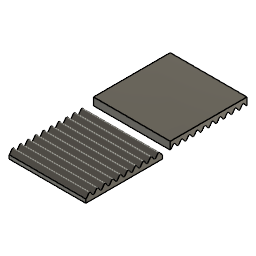
Mould texture v1 (Autodesk Fusion 360 design; units mm, degrees)
part number: 2026-06-02-12-18-22-877
Autodesk Fusion 360 part; units mm, degrees
sketch "Sketch1" plane through (0, 0, 0) normal (1, 0, 0) x (0, 1, 0)
  line L0 (0, 0) -> (100, 0)
  spline S0 degree 5 poles (0, 5) (0.1905, 5) (0.5782, 5.1) (1.1803, 5.55) (2.0142, 6.654) (3.0561, 8.346) (4.0573, 9.726) (4.9964, 10.266) (5.9504, 9.726) (6.9802, 8.346) (8.0326, 6.654) (9.0551, 5.274) (9.9993, 4.734) (10.9464, 5.274) (11.9742, 6.654) (13.0285, 8.346) (14.0548, 9.726) (14.9998, 10.266) (15.9457, 9.726) (16.9738, 8.346) (18.0288, 6.654) (19.0554, 5.274) (19.9994, 4.734) (20.9459, 5.274) (21.9778, 6.654) (23.0362, 8.346) (24.0625, 9.726) (25, 10.266) (25.9375, 9.726) (26.9638, 8.346) (28.0222, 6.654) (29.0541, 5.274) (30.0006, 4.734) (30.9447, 5.274) (31.9714, 6.654) (33.0264, 8.346) (34.0544, 9.726) (35.0001, 10.266) (35.9453, 9.726) (36.9723, 8.346) (38.027, 6.654) (39.0544, 5.274) (40.0001, 4.734) (40.9454, 5.274) (41.9718, 6.654) (43.0261, 8.3459) (44.0537, 9.7259) (45.0006, 10.266) (45.945, 9.726) (46.9676, 8.3457) (48.0187, 6.6535) (49.0469, 5.2736) (50.0003, 4.734) (50.9524, 5.2744) (51.9779, 6.6545) (53.028, 8.3462) (54.0524, 9.726) (55.0013, 10.266) (55.9449, 9.726) (56.9582, 8.346) (58.0016, 6.6539) (59.0314, 5.2739) (60.0013, 4.734) (60.9659, 5.2741) (61.9848, 6.6542) (63.0217, 8.3461) (64.0396, 9.726) (65.0008, 10.266) (65.9588, 9.726) (66.9699, 8.346) (68.0023, 6.654) (69.0234, 5.274) (69.9988, 4.734) (70.9793, 5.274) (72.0109, 6.654) (73.0496, 8.346) (74.0564, 9.726) (74.9974, 10.266) (75.9491, 9.726) (76.9782, 8.346) (78.0311, 6.654) (79.0549, 5.274) (79.9995, 4.734) (80.9461, 5.274) (81.9735, 6.654) (83.0278, 8.346) (84.0544, 9.726) (85, 10.266) (85.9455, 9.726) (86.9719, 8.346) (88.0261, 6.654) (89.0537, 5.274) (90.0006, 4.734) (90.945, 5.274) (91.9675, 6.654) (93.0199, 8.346) (94.0496, 9.726) (95.0036, 10.266) (95.9427, 9.726) (96.9439, 8.346) (97.9858, 6.654) (98.8197, 5.55) (99.4218, 5.1) (99.8095, 5) (100, 5) knots 0 0 0 0 0 0 0.01 0.02 0.03 0.04 0.05 0.06 0.07 0.08 0.09 0.1 0.11 0.12 0.13 0.14 0.15 0.16 0.17 0.18 0.19 0.2 0.21 0.22 0.23 0.24 0.25 0.26 0.27 0.28 0.29 0.3 0.31 0.32 0.33 0.34 0.35 0.36 0.37 0.38 0.39 0.4 0.41 0.42 0.43 0.44 0.45 0.46 0.47 0.48 0.49 0.5 0.51 0.52 0.53 0.54 0.55 0.56 0.57 0.58 0.59 0.6 0.61 0.62 0.63 0.64 0.65 0.66 0.67 0.68 0.69 0.7 0.71 0.72 0.73 0.74 0.75 0.76 0.77 0.78 0.79 0.8 0.81 0.82 0.83 0.84 0.85 0.86 0.87 0.88 0.89 0.9 0.91 0.92 0.93 0.94 0.95 0.96 0.97 0.98 0.99 1 1 1 1 1 1
  line L1 (89, 10) -> (101, 10)
  line L2 (94, 5) -> (106, 5)
  line L3 (84, 5) -> (96, 5)
  line L4 (79, 10) -> (91, 10)
  line L5 (74, 5) -> (86, 5)
  line L6 (69, 10) -> (81, 10)
  line L7 (63.8128, 4.9999) -> (76.1872, 5.0001)
  line L8 (58.925, 10.0003) -> (71.075, 9.9997)
  line L9 (53.8758, 4.9994) -> (66.1242, 5.0006)
  line L10 (49, 10) -> (61, 10)
  line L11 (43.9583, 4.9975) -> (56.0417, 5.0025)
  line L12 (39, 10) -> (51, 10)
  line L13 (34, 5) -> (46, 5)
  line L14 (29, 10) -> (41, 10)
  line L15 (24, 5) -> (36, 5)
  line L16 (19.0467, 10) -> (30.9533, 10)
  line L17 (14, 5) -> (26, 5)
  line L18 (9, 10) -> (21, 10)
  line L19 (4, 5) -> (16, 5)
  line L20 (-1, 10) -> (11, 10)
  line L21 (-6, 5) -> (6, 5)
  line L22 (0, 5) -> (0, 0)
  line L23 (100, 5) -> (100, 0)
  line L24 (0, 5) -> (0, 15)
  line L25 (0, 15) -> (100, 15)
  line L26 (100, 15) -> (100, 5)
  point P0 (5, 10)
  point P1 (10, 5)
  point P2 (15, 10)
  point P3 (20, 5)
  point P4 (25, 10)
  point P5 (30, 5)
  point P6 (35, 10)
  point P7 (40, 5)
  point P8 (45, 10)
  point P9 (50, 5)
  point P10 (55, 10)
  point P11 (60, 5)
  point P12 (65, 10)
  point P13 (70, 5)
  point P14 (75, 10)
  point P15 (80, 5)
  point P16 (85, 10)
  point P17 (90, 5)
  point P18 (95, 10)
  constraint coincident L0.start L22.end
  constraint horizontal L0
  constraint midpoint P18 L1
  constraint midpoint S0.end L2
  constraint midpoint P17 L3
  constraint midpoint P16 L4
  constraint midpoint P15 L5
  constraint coincident L2.start L3
  constraint parallel L2 L3
  constraint midpoint P14 L6
  constraint midpoint P13 L7
  constraint midpoint P12 L8
  constraint midpoint P11 L9
  constraint midpoint P10 L10
  constraint midpoint P9 L11
  constraint midpoint P8 L12
  constraint midpoint P7 L13
  constraint midpoint P6 L14
  constraint midpoint P5 L15
  constraint midpoint P4 L16
  constraint midpoint P3 L17
  constraint midpoint P2 L18
  constraint midpoint P1 L19
  constraint midpoint P0 L20
  constraint midpoint S0.start L21
  constraint coincident L19 L21.end
  constraint parallel L19 L21
  constraint perpendicular L0 L22
  constraint parallel L22 L24
  constraint perpendicular L24 L25
  constraint perpendicular L25 L26
extrude "Extrude1" add sketch "Sketch1" along normal blind 100 contours S0 L20 L24 | S0 L1 L26 | S0 L18 L20 | L1 L4 L6 L8 L10 L12 L14 L16 L18 L20 L24 L25 L26 | S0 L1 L4 | S0 L16 L18 | S0 L4 L6 | S0 L14 L16 | S0 L6 L8 | S0 L12 L14 | S0 L8 L10 | S0 L10 L12 makes body 1
extrude "Extrude2" add sketch "Sketch1" against normal blind 100 separate body contours L0 S0 L2 L3 L5 L7 L9 L11 L13 L15 L17 L19 L21 L22 L23 | S0 L19 L21 | S0 L2 L3 | S0 L17 L19 | S0 L3 L5 | S0 L15 L17 | S0 L5 L7 | S0 L13 L15 | S0 L7 L9 | S0 L11 L13 makes body 2
move_face "MoveFace1" by (-100, 110, 0) 1 faces at (33.3333, 33.3333, 15) on bodies 1
move_body "Move1" bodies 1 to x (1, 0, 0) y (0, 1, 0) z (0, 0, 1) at (0, 110, 0)
move_body "Move2" bodies 1 to x (1, 0, 0) y (0, 1, 0) z (0, 0, 1) at (-100, 0, 0)
